Untitled (mgXIKuq5) (Autodesk Fusion 360 design; units mm, degrees)
Autodesk Fusion 360 part; units mm, degrees
sketch "Sketch1" plane through (0, 0, 0) normal (0, 1, 0) x (1, 0, 0)
  line L0 (45, -75) -> (-45, -75)
  line L1 (-45, -75) -> (-45, 75)
  line L2 (-45, 75) -> (45, 75)
  line L3 (45, 75) -> (45, -75)
  line L4 (45, -75) -> (-45, 75) construction
  line L5 (-45, -75) -> (45, 75) construction
  line L6 (40, -70) -> (-40, -70)
  line L7 (-40, -70) -> (-40, 70)
  line L8 (-40, 70) -> (40, 70)
  line L9 (40, 70) -> (40, -70)
  line L10 (40, -70) -> (-40, 70) construction
  line L11 (-40, -70) -> (40, 70) construction
  dimension "d1" = 90
  dimension "d2" = 150
  dimension "d3" = 80
  dimension "d4" = 140
  constraint perpendicular L0 L1
  constraint parallel L0 L2
  constraint parallel L1 L3
  constraint horizontal L0
  constraint coincident L4 origin
  constraint coincident L5 origin
  constraint perpendicular L6 L7
  constraint parallel L6 L8
  constraint parallel L7 L9
  constraint horizontal L6
  constraint coincident L10 origin
  constraint coincident L11 origin
  measures "d1" distance of L1.end L2.end
  measures "d2" distance of L0.end L1.end
  measures "d3" distance of L7.end L8.end
  measures "d4" distance of L6.end L7.end
extrude "Extrude1" add sketch "Sketch1" along normal blind 10
fillet "Fillet1" radius 5 8 edges at (-45, 5, 75) (-40, 5, 70) (40, 5, 70) (45, 5, 75) (45, 5, -75) (-45, 5, -75) (-40, 5, -70) (40, 5, -70)
